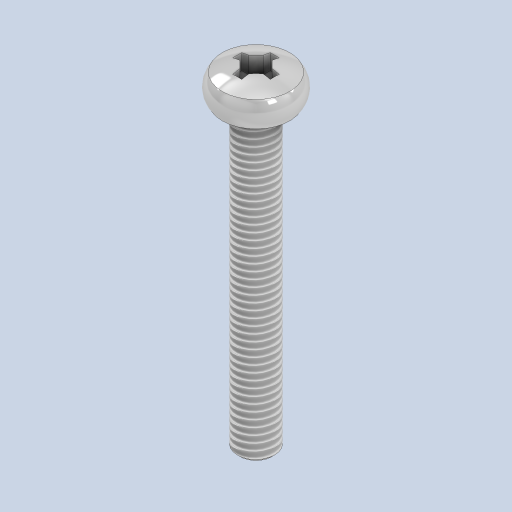
# Autodesk Inventor part: Parafuso 2,5 x 20mm
Saved by Autodesk Inventor 2024.3 (Build 283343000, 343)
## iProperties
Created: 2025-02-16
Part Number: Parafuso 2,5 x 20mm
Material: Aço
Document SubType Name: Modeling
Designer: Cliente
Density: 7.85 g/cm^3
Appearance: Alumínio - Polido
Mass: 1.02659 g
Surface Area: 2.26342 cm^2
Volume: 0.130776 cm^3
Author: Cliente
Autodesk Inventor part; units mm, degrees
ref_plane "YZ Plane" through (0, 0, 0) normal (1, 0, 0) x (0, 1, 0)
ref_plane "XY Plane" through (0, 0, 0) normal (0, 0, 1) x (1, 0, 0)
sketch "Esboço1" plane through (0, 0, 0) normal (0, 1, 0) x (-1, 0, 0)
  circle A0 centre (0, 0) radius 1.25
  dimension "d0" = 2.5
  constraints: 1 centre point, 1 coincident
  measures "d0" diameter of A0
extrude "Extrusão1" add sketch "Esboço1" against normal blind 20
sketch "Esboço2" plane through (0, 0, 0) normal (1, 0, 0) x (0, 1, 0)
  line L0 (0, 0) -> (0, 2.55)
  line L1 (0, 2.55) -> (2.2, 2.55)
  line L2 (2.2, 2.55) -> (2.2, 0)
  line L3 (2.2, 0) -> (0, 0)
  line L4 (2.2, 2.25) -> (1.7, 2.25)
  arc A0 (2.2, 0) -> (1.7, 2.25) centre (-3.1125, 0) ccw
  line L5 (1.7, 2.25) -> (0, 2.25)
  arc A1 (1.7, 2.25) -> (0, 2.25) centre (0.85, 1.1958) ccw
  dimension "d3" = 2.55
  dimension "d4" = 2.2
  dimension "d5" = 0.5
  dimension "d7" = 0.3
  constraints: 12 end point, 4 perpendicular, 4 point on circle, 2 centre point, 2 point on line, 2 tangent, 1 horizontal, 1 vertical
  measures "d3" distance of L0.start L0.end
  measures "d4" distance of L0.end L1.end
  measures "d5" distance of L4.start L4.end
  measures "d7" distance between parallel lines of L1 L4
revolve "Revolução1" add sketch "Esboço2" angle 360 about axis through (0, 2.2, 0) along (0, -1, 0) contours L0 L5 A0 L3 | A1 L5
thread "Rosca1" size "M2.5x0.45" class "6g" standard "ANSI Metric M Profile" length 20
fillet "Arredondamento1" radius 0.1 1 edges at (1.25, 0, 0)
chamfer "Chanfro1" distance 0.2 angle 45 1 edges at (1.25, -20, 0)
ref_plane "Plano de trabalho1" through (0, 2.2, 0) normal (0, 1, 0) x (-1, 0, 0)
sketch "Esboço3" plane through (0, 2.2, 0) normal (0, 1, 0) x (-1, 0, 0)
  line L0 (-1.25, 0.3) -> (1.25, 0.3)
  line L1 (1.25, 0.3) -> (1.25, -0.3)
  line L2 (1.25, -0.3) -> (-1.25, -0.3)
  line L3 (-1.25, -0.3) -> (-1.25, 0.3)
  line L4 (-1.25, 0.3) -> (1.25, -0.3) construction
  line L5 (1.25, 0.3) -> (-1.25, -0.3) construction
  line L6 (-0.3, 1.25) -> (0.3, 1.25)
  line L7 (0.3, 1.25) -> (0.3, -1.25)
  line L8 (0.3, -1.25) -> (-0.3, -1.25)
  line L9 (-0.3, -1.25) -> (-0.3, 1.25)
  circle A0 centre (0, 0) radius 1.35 projected
  line L10 (-0.3, 1.25) -> (0.3, -1.25) construction
  line L11 (0.3, 1.25) -> (-0.3, -1.25) construction
  line L12 (1.25, 0.3) -> (0.3, 0.3)
  line L13 (0.3, 1.25) -> (0.3, 0.3)
  line L14 (0.775, 0.3) -> (0.3, 0.775)
  line L15 (-0.3, 0.775) -> (-0.775, 0.3)
  line L16 (-0.775, -0.3) -> (-0.3, -0.775)
  line L17 (0.3, -0.775) -> (0.775, -0.3)
  point P0 (-0.775, 0.3)
  point P1 (-0.3, -0.775)
  dimension "d15" = 2.5
  dimension "d16" = 0.6
  dimension "d17" = 0.6
  dimension "d18" = 2.5
  dimension "d21" = 360
  constraints: 36 end point, 6 midpoint, 4 parallel, 2 horizontal, 2 perpendicular, 2 point on line, 1 collinear, 13 other
  measures "d15" distance of L1.end L2.end
  measures "d16" distance of L0.end L1.end
  measures "d17" distance of L7.end L8.end
  measures "d18" distance of L6.end L7.end
extrude "Extrusão2" cut sketch "Esboço3" against normal blind 1.2 contours L0 L9 L2 L3 | L15 L9 L0 | L9 L6 L7 L0 | L0 L7 L2 L9 | L2 L9 L16 | L7 L14 L0 | L0 L1 L2 L7 | L2 L7 L8 L9 | L2 L17 L7
